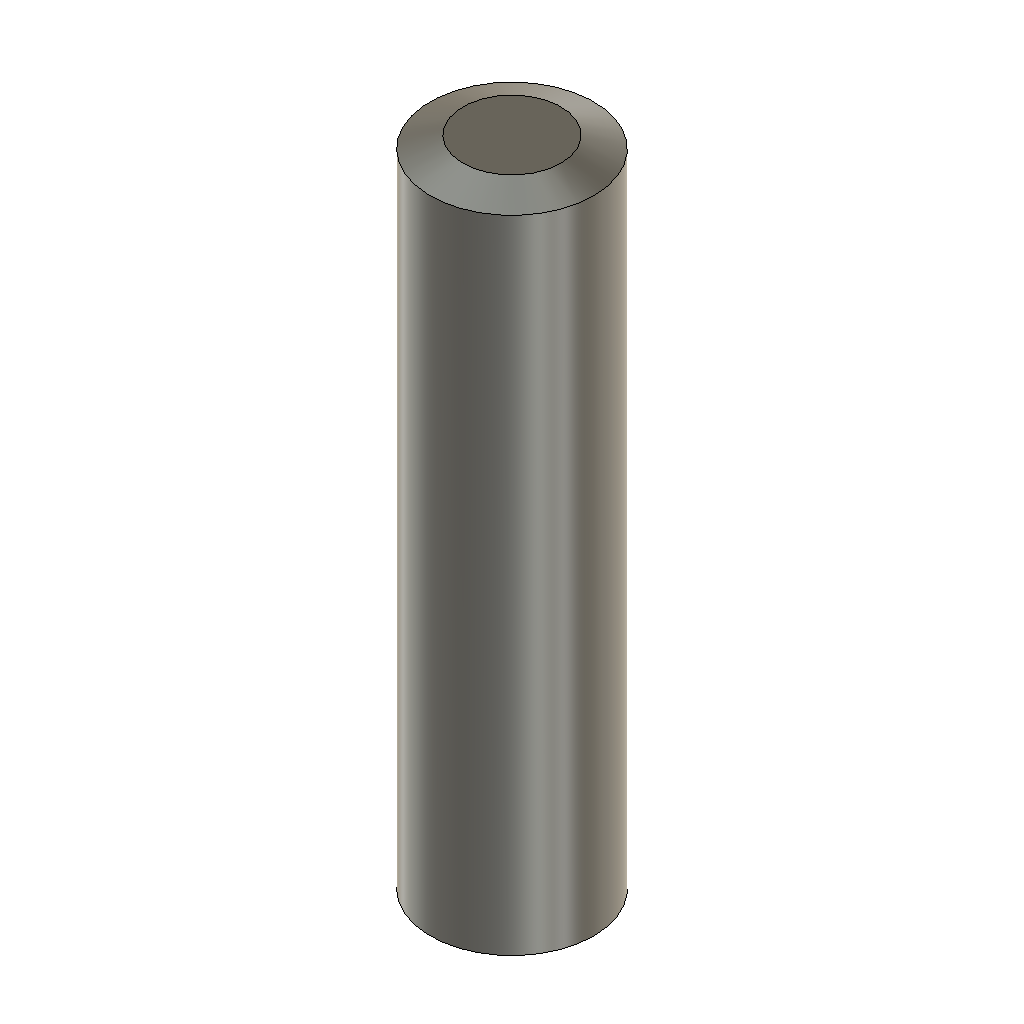
dr341-chamfer-cyl (Autodesk Fusion 360 design; units mm, degrees)
part number: 2026-11-15-17-09-48-773
Autodesk Fusion 360 part; units mm, degrees
cylinder "CylinderPrimitive1" add diameter 5 height 20 placed x (1, 0, 0) y (0, 1, 0) z (0, 0, 1) at (0, 0, 0)
chamfer "Chamfer1" distance 1 angle 20 1 edges at (-2.3308, -0.904, 20) measured on face at (-0.8863, 0.2321, 20) tangent chain off
